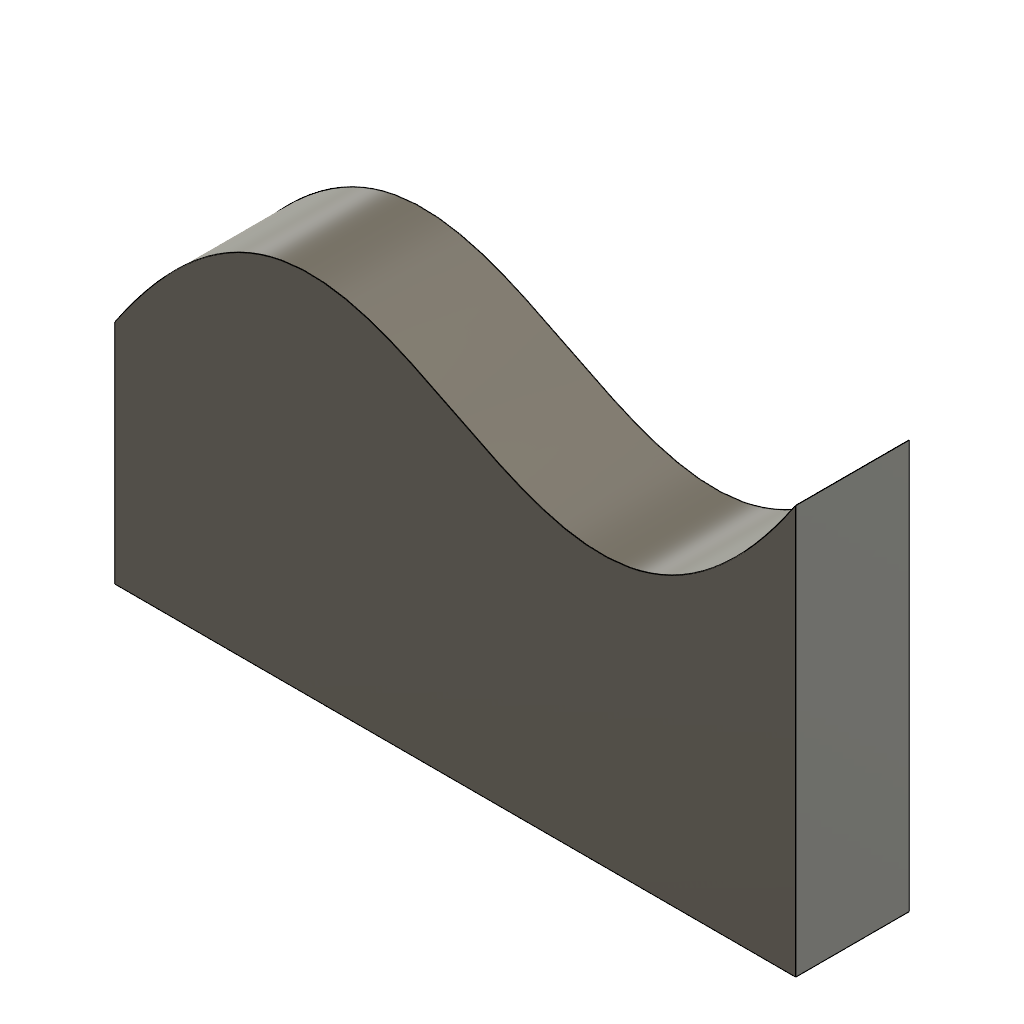
sk_spline_fit (Autodesk Fusion 360 design; units mm, degrees)
part number: 2026-11-13-14-35-09-693
Autodesk Fusion 360 part; units mm, degrees
sketch "Sketch1" plane through (0, 0, 0) normal (0, 0, 1) x (1, 0, 0)
  spline S0 degree 5 poles (0, 0) (0.3826, 0.5717) (1.1502, 1.6488) (2.3091, 3.0655) (3.8694, 4.5536) (5.845, 5.7387) (7.8455, 6.2575) (9.8694, 6.1535) (11.9129, 5.5246) (13.9695, 4.5485) (16.0305, 3.4515) (18.0871, 2.4754) (20.1306, 1.8465) (22.1545, 1.7425) (24.155, 2.2613) (26.1306, 3.4464) (27.6909, 4.9345) (28.8498, 6.3512) (29.6174, 7.4283) (30, 8) knots 0 0 0 0 0 0 0.066667 0.133333 0.2 0.266667 0.333333 0.4 0.466667 0.533333 0.6 0.666667 0.733333 0.8 0.866667 0.933333 1 1 1 1 1 1
  line L0 (30, 8) -> (30, -10)
  line L1 (30, -10) -> (0, -10)
  line L2 (0, -10) -> (0, 0)
  point P0 (10, 6)
  point P1 (20, 2)
extrude "Extrude1" add sketch "Sketch1" along normal blind 5
